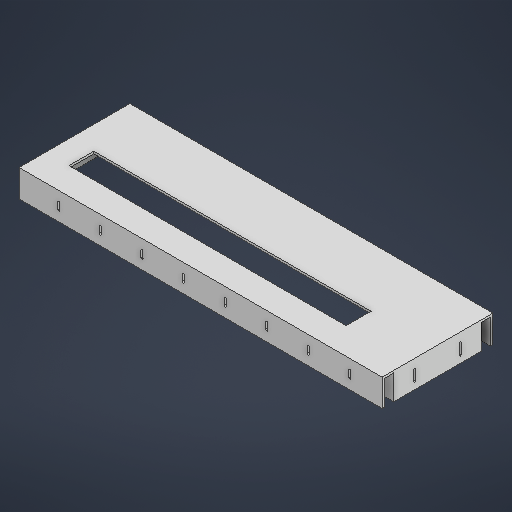
# Autodesk Inventor part: Papel_v0
Saved by Autodesk Inventor 2027 (Build 310192060, 192F)
## iProperties
Created: 2026-10-12
Part Number: Papel_v0
Material: Generic
Document SubType Name: Modeling
Designer: Pablo
Density: 1 g/cm^3
Appearance: Default
Author: Pablo
Autodesk Inventor part; units mm, degrees
ref_plane "YZ Plane" through (0, 0, 0) normal (1, 0, 0) x (0, 1, 0)
ref_plane "XZ Plane" through (0, 0, 0) normal (0, 1, 0) x (-1, 0, 0)
sketch "Sketch1" plane through (0, 0, 0) normal (0, 1, 0) x (-1, 0, 0)
  line L0 (-327.5, -100) -> (327.5, -100)
  line L1 (327.5, -100) -> (327.5, 100)
  line L2 (327.5, 100) -> (-327.5, 100)
  line L3 (-327.5, 100) -> (-327.5, -100)
  line L4 (-327.5, -100) -> (327.5, 100) construction
  line L5 (327.5, -100) -> (-327.5, 100) construction
  line L6 (-214.5, 100) -> (-214.5, 52) construction
  line L7 (-327.5, 52) -> (-214.5, 52) construction
  line L8 (-214.5, 52) -> (285.5, 52)
  line L9 (285.5, 52) -> (285.5, 7)
  line L10 (285.5, 7) -> (-214.5, 7)
  line L11 (-214.5, 7) -> (-214.5, 52)
  point P0 (0, 0)
  dimension "d6" = 200
  dimension "d13" = 48
  dimension "d14" = 113
  dimension "d15" = 500
  dimension "d16" = 45
  dimension "d17" = 655
  constraints: 24 end point, 5 parallel, 3 horizontal, 2 midpoint, 2 perpendicular, 2 point on line
  measures "d6" distance of L0.end L1.end
  measures "d13" distance of L6.end L6.start
  measures "d14" distance of L7.start L6.end
  measures "d15" distance of L9.end L10.end
  measures "d16" distance of L8.end L9.end
  measures "d17" distance of L1.end L2.end
extrude "Extrusion1" add sketch "Sketch1" along normal blind 4
ref_plane "Work Plane1" through (-35.5, 4, 29.5) normal (0, 0, 1) x (1, 0, 0)
sketch "Sketch2" plane through (0, 0, 0) normal (0, -1, 0) x (1, 0, 0)
  line L0 (-327.5, -100) -> (-327.5, 100) projected
  line L1 (327.5, -100) -> (-327.5, -100) projected
  line L2 (-327.5, 100) -> (327.5, 100) projected
  line L3 (327.5, -100) -> (327.5, -95)
  line L4 (327.5, -95) -> (-322.5, -95)
  line L5 (-322.5, -95) -> (-322.5, 95)
  line L6 (-322.5, 95) -> (327.5, 95)
  line L7 (327.5, 95) -> (327.5, 100)
  point P0 (0, 0)
  dimension "d25" = 5
  dimension "d26" = 5
  dimension "d27" = 5
  constraints: 10 end point, 3 perpendicular, 1 parallel, 1 point on line, 1 vertical
  measures "d25" distance between parallel lines of L2 L6
  measures "d26" distance between parallel lines of L0 L5
  measures "d27" distance between parallel lines of L1 L4
extrude "Extrusion2" add sketch "Sketch2" along normal blind 45
sketch "Sketch3" plane through (-327.5, 4, 100) normal (0, 0, 1) x (1, 0, 0)
  line L0 (0, -49) -> (0, 0) construction
  line L1 (0, -24.5) -> (733.2958, -24.5)
  line L2 (71.75, -18.5) -> (71.75, -30.5) construction
  line L3 (70, -18.5) -> (70, -30.5)
  line L4 (73.5, -30.5) -> (73.5, -18.5)
  arc A0 (73.5, -18.5) -> (70, -18.5) centre (71.75, -18.5) ccw
  arc A1 (70, -30.5) -> (73.5, -30.5) centre (71.75, -30.5) ccw
  line L5 (145, -18.5) -> (145, -30.5)
  line L6 (75, -24.5) -> (808.2958, -24.5)
  arc A2 (148.5, -18.5) -> (145, -18.5) centre (146.75, -18.5) ccw
  line L7 (148.5, -30.5) -> (148.5, -18.5)
  arc A3 (145, -30.5) -> (148.5, -30.5) centre (146.75, -30.5) ccw
  line L8 (220, -18.5) -> (220, -30.5)
  line L9 (150, -24.5) -> (883.2958, -24.5)
  arc A4 (223.5, -18.5) -> (220, -18.5) centre (221.75, -18.5) ccw
  line L10 (223.5, -30.5) -> (223.5, -18.5)
  arc A5 (220, -30.5) -> (223.5, -30.5) centre (221.75, -30.5) ccw
  line L11 (295, -18.5) -> (295, -30.5)
  line L12 (225, -24.5) -> (958.2958, -24.5)
  arc A6 (298.5, -18.5) -> (295, -18.5) centre (296.75, -18.5) ccw
  line L13 (298.5, -30.5) -> (298.5, -18.5)
  arc A7 (295, -30.5) -> (298.5, -30.5) centre (296.75, -30.5) ccw
  line L14 (370, -18.5) -> (370, -30.5)
  line L15 (300, -24.5) -> (1033.2958, -24.5)
  arc A8 (373.5, -18.5) -> (370, -18.5) centre (371.75, -18.5) ccw
  line L16 (373.5, -30.5) -> (373.5, -18.5)
  arc A9 (370, -30.5) -> (373.5, -30.5) centre (371.75, -30.5) ccw
  line L17 (445, -18.5) -> (445, -30.5)
  line L18 (375, -24.5) -> (1108.2958, -24.5)
  arc A10 (448.5, -18.5) -> (445, -18.5) centre (446.75, -18.5) ccw
  line L19 (448.5, -30.5) -> (448.5, -18.5)
  arc A11 (445, -30.5) -> (448.5, -30.5) centre (446.75, -30.5) ccw
  line L20 (520, -18.5) -> (520, -30.5)
  line L21 (450, -24.5) -> (1183.2958, -24.5)
  arc A12 (523.5, -18.5) -> (520, -18.5) centre (521.75, -18.5) ccw
  line L22 (523.5, -30.5) -> (523.5, -18.5)
  arc A13 (520, -30.5) -> (523.5, -30.5) centre (521.75, -30.5) ccw
  line L23 (595, -18.5) -> (595, -30.5)
  line L24 (525, -24.5) -> (1258.2958, -24.5)
  arc A14 (598.5, -18.5) -> (595, -18.5) centre (596.75, -18.5) ccw
  line L25 (598.5, -30.5) -> (598.5, -18.5)
  arc A15 (595, -30.5) -> (598.5, -30.5) centre (596.75, -30.5) ccw
  point P0 (327.5, -4)
  point P1 (71.75, -24.5)
  point P2 (146.75, -24.5)
  point P3 (221.75, -24.5)
  point P4 (296.75, -24.5)
  point P5 (371.75, -24.5)
  point P6 (446.75, -24.5)
  point P7 (521.75, -24.5)
  point P8 (596.75, -24.5)
  dimension "d28" = 3.5
  dimension "d29" = 12
  dimension "d32" = 75
  dimension "d37" = 70
  constraints: 52 end point, 32 point on circle, 16 centre point, 8 point on line, 4 tangent, 2 horizontal, 2 midpoint, 1 collinear, 1 parallel, 1 perpendicular, 97 other
  measures "d28" distance between parallel lines of L3 L4
  measures "d29" distance of L4.start L4.end
  measures "d32" distance of L3.start L5.start
  measures "d37" distance between parallel lines of L0 L3
extrude "Extrusion3" cut sketch "Sketch3" against normal through all
sketch "Sketch4" plane through (0, 0, 0) normal (0, -1, 0) x (1, 0, 0)
  line L0 (327.5, 95) -> (327.5, -95) construction
  line L1 (327.5, -79) -> (302.5, -79)
  line L2 (302.5, -79) -> (302.5, -74)
  line L3 (302.5, -74) -> (317.5, -74)
  line L4 (317.5, -74) -> (317.5, 74)
  line L5 (317.5, 74) -> (302.5, 74)
  line L6 (302.5, 74) -> (302.5, 79)
  line L7 (302.5, 79) -> (327.5, 79)
  line L8 (327.5, -79) -> (327.5, 79)
  line L9 (0, 0) -> (393.4835, 0)
  line L10 (327.5, -95) -> (-322.5, -95) construction
  dimension "d40" = 16
  dimension "d41" = 10
  dimension "d42" = 5
  dimension "d43" = 25
  constraints: 18 end point, 6 perpendicular, 2 horizontal, 2 point on line, 1 collinear, 3 other
  measures "d40" distance between parallel lines of L10 L1
  measures "d41" distance between parallel lines of L0 L4
  measures "d42" distance between parallel lines of L1 L3
  measures "d43" distance between parallel lines of L0 L2
extrude "Extrusion4" add sketch "Sketch4" along normal up to surface (45 mm away)
sketch "Sketch5" plane through (327.5, 4, 100) normal (1, 0, 0) x (0, 0, -1)
  line L0 (179, -4) -> (179, -49) construction
  line L1 (21, -4) -> (21, -49) construction
  line L2 (100, -4) -> (100, -88.4561)
  line L3 (179, -26.5) -> (21, -26.5)
  line L4 (141.25, -16.5) -> (141.25, -36.5) construction
  line L5 (140, -16.5) -> (140, -36.5)
  line L6 (142.5, -36.5) -> (142.5, -16.5)
  arc A0 (142.5, -16.5) -> (140, -16.5) centre (141.25, -16.5) ccw
  arc A1 (140, -36.5) -> (142.5, -36.5) centre (141.25, -36.5) ccw
  line L7 (60, -16.5) -> (60, -36.5)
  line L8 (57.5, -36.5) -> (57.5, -16.5)
  arc A2 (60, -16.5) -> (57.5, -16.5) centre (58.75, -16.5) ccw
  arc A3 (57.5, -36.5) -> (60, -36.5) centre (58.75, -36.5) ccw
  point P0 (141.25, -26.5)
  dimension "d46" = 10
  dimension "d47" = 2.5
  dimension "d48" = 80
  constraints: 16 end point, 8 point on circle, 6 symmetric about line, 4 centre point, 4 tangent, 3 midpoint, 1 parallel, 1 perpendicular, 1 point on line, 1 vertical, 2 other
  measures "d46" distance of point (141.25, -26.5) L4.end
  measures "d47" diameter of A1
  measures "d48" distance between parallel lines of L7 L5
extrude "Extrusion5" cut sketch "Sketch5" against normal up to surface (10 mm away)
sketch "Sketch6" plane through (0, 0, 0) normal (0, -1, 0) x (1, 0, 0)
  line L0 (327.5, -95) -> (-322.5, -95) construction
  line L1 (-322.5, -95) -> (-322.5, 95) construction
  line L2 (-322.5, 95) -> (327.5, 95) construction
  line L3 (-322.5, 95) -> (-322.5, -95) projected
  line L4 (-322.5, -79) -> (-297.5, -79)
  line L5 (-297.5, -79) -> (-297.5, -74)
  line L6 (-297.5, -74) -> (-322.5, -74)
  line L7 (-322.5, 74) -> (-297.5, 74)
  line L8 (-297.5, 74) -> (-297.5, 79)
  line L9 (-297.5, 79) -> (-322.5, 79)
  line L10 (-322.5, 0) -> (-254.9864, 0)
  line L11 (-322.5, -79) -> (-322.5, -74)
  line L12 (-322.5, 74) -> (-322.5, 79)
  point P0 (0, 0)
  dimension "d51" = 16
  dimension "d52" = 5
  dimension "d53" = 25
  constraints: 18 end point, 6 perpendicular, 4 point on line, 2 horizontal, 1 collinear, 1 midpoint, 3 other
  measures "d51" distance between parallel lines of L0 L4
  measures "d52" distance between parallel lines of L4 L6
  measures "d53" distance between parallel lines of L1 L5
extrude "Extrusion6" add sketch "Sketch6" along normal up to surface (45 mm away)
chamfer "Chamfer1" distance 10 angle 45 2 edges at (-322.5, -22.5, 74) (-322.5, -22.5, -74)
body "Solid1"
